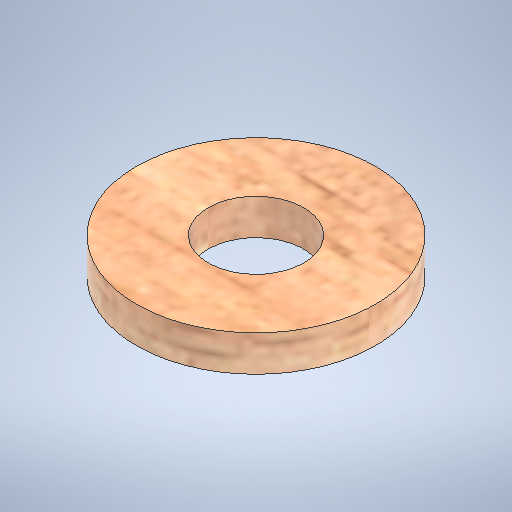
# Autodesk Inventor part: CIRCULAR BOARD 6mm
Saved by Autodesk Inventor 2026.2 (Build 302298000, 298)
## iProperties
Created: 2026-07-27
Part Number: CIRCULAR BOARD 6mm
Material: Wood (Birch)
Document SubType Name: Modeling
Designer: Taiye Raji
Density: 0.6 g/cm^3
Appearance: Birch - Natural Polished
Mass: 10.7669 g
Surface Area: 51.0195 cm^2
Volume: 17.9448 cm^3
Author: Taiye Raji
Autodesk Inventor part; units mm, degrees
ref_plane "YZ Plane" through (0, 0, 0) normal (1, 0, 0) x (0, 1, 0)
ref_plane "XZ Plane" through (0, 0, 0) normal (0, 1, 0) x (-1, 0, 0)
ref_plane "XY Plane" through (0, 0, 0) normal (0, 0, 1) x (1, 0, 0)
sketch "Sketch1" plane through (0, 0, 0) normal (0, 1, 0) x (-1, 0, 0)
  circle A0 centre (0, 0) radius 20
  circle A1 centre (0, 0) radius 8
  dimension "d0" = 16
  dimension "d1" = 40
  constraints: 2 centre point, 2 coincident
  measures "d0" diameter of A1
  measures "d1" diameter of A0
extrude "Extrusion1" add sketch "Sketch1" along normal blind 6
body "Solid1"
